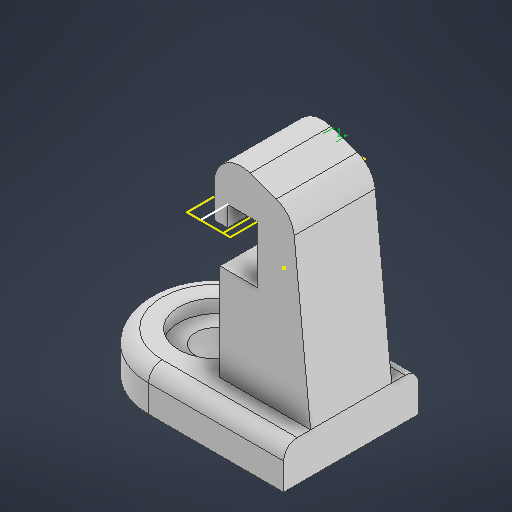
# Autodesk Inventor part: zaczep_baterie
Saved by Autodesk Inventor 2026.1 (Build 301233020, 233B)
## iProperties
Created: 2026-08-01
Part Number: zaczep_baterie
Material: Ogólny
Document SubType Name: Modeling
Designer: Nitro
Density: 1 g/cm^3
Appearance: Domyślna
Author: Nitro
Autodesk Inventor part; units mm, degrees
ref_plane "YZ Plane" through (0, 0, 0) normal (1, 0, 0) x (0, 1, 0)
ref_plane "XZ Plane" through (0, 0, 0) normal (0, 1, 0) x (-1, 0, 0)
ref_plane "XY Plane" through (0, 0, 0) normal (0, 0, 1) x (1, 0, 0)
sketch "Szkic1" plane through (0, 0, 0) normal (0, 1, 0) x (-1, 0, 0)
  line L0 (0, 0) -> (10, 0)
  line L1 (10, 0) -> (10, -10)
  line L2 (10, -10) -> (0, -10)
  line L3 (0, -10) -> (0, 0)
  arc A0 (10, -10) -> (10, 0) centre (10, -5) ccw
  circle A1 centre (10, -5) radius 1.5
  dimension "d0" = 10
  dimension "d1" = 10
  dimension "d2" = 3
  constraints: 8 end point, 2 centre point, 2 parallel, 2 point on circle, 2 tangent, 1 coincident, 1 horizontal, 1 perpendicular
  measures "d0" distance of L1.end L2.end
  measures "d1" distance of L0.end L1.end
  measures "d2" diameter of A1
extrude "Wyciągnięcie proste1" add sketch "Szkic1" along normal blind 3 contours L0 L1 A1 L2 L3 | A0 L1 A1
sketch "Szkic2" plane through (0, 0, -10) normal (0, 0, -1) x (-1, 0, 0)
  line L0 (0, 0) -> (10, 0) projected
  line L1 (10, 0) -> (10, 3) projected
  line L2 (0, 3) -> (10, 3) projected
  line L3 (0, 0) -> (0, 3) projected
  line L4 (10, 3) -> (0, 3) projected
  line L5 (0, 3) -> (1.3424, 16.1037)
  line L6 (1.3424, 16.1037) -> (7.148, 18.1599)
  line L7 (6.7175, 3) -> (6.7175, 10.1512)
  line L8 (6.7175, 10.1512) -> (3.9483, 10.1512)
  line L9 (3.9483, 10.1512) -> (3.9483, 14.3731)
  line L10 (3.9483, 14.3731) -> (7.148, 14.3731)
  line L11 (7.148, 14.3731) -> (7.148, 18.1599)
  constraints: 14 end point, 4 perpendicular, 1 point on line, 1 vertical
extrude "Wyciągnięcie proste2" add sketch "Szkic2" against normal blind 10 contours L5 L6 L11 L10 L9 L8 L7 L2
fillet "Zaokrąglenie1" radius 2 2 edges at (-1.3424, 16.1037, -5) (-7.148, 18.1599, -5)
sketch "Szkic3" plane through (0, 3, 0) normal (0, 1, 0) x (1, 0, 0)
  circle A0 centre (-10, 5) radius 1.5 projected
  line L0 (-6.7175, 0) -> (-6.7175, 10) projected
  line L1 (-6.7175, 10) -> (-10, 10) projected
  arc A1 (-10, 10) -> (-10, 0) centre (-10, 5) ccw projected
  line L2 (-10, 0) -> (-6.7175, 0) projected
  circle A2 centre (-10, 5) radius 2.75
  point P0 (0, 0)
  dimension "d8" = 5.5
  constraints: 1 centre point, 1 coincident
  measures "d8" diameter of A2
extrude "Wyciągnięcie proste3" cut sketch "Szkic3" against normal blind 1 contours A2
sketch "Szkic4" plane through (-7.148, 14.3731, -10) normal (0, -1, 0) x (1, 0, 0)
  line L0 (2.6677, 10) -> (2.6677, 0) projected
  line L1 (3.1997, 0) -> (0, 0) projected
  line L2 (3.1997, 0) -> (3.1997, 10) projected
  line L3 (0, 10) -> (3.1997, 10) projected
  line L4 (0, 0) -> (0, 10) projected
  line L5 (0, 10) -> (1, 10)
  line L6 (1, 10) -> (1, 0)
  line L7 (1, 0) -> (0, 0)
  line L8 (0, 0) -> (0, 10)
  point P0 (7.148, 10)
  dimension "d11" = 1
  constraints: 8 end point, 2 parallel, 1 horizontal, 1 perpendicular, 1 point on line
  measures "d11" distance of L6.end L7.end
sketch "Szkic5" plane through (0, 0, -10) normal (0, 0, -1) x (-1, 0, 0)
  arc A0 (7.148, 15.3298) -> (4.4803, 17.2151) centre (5.148, 15.3298) ccw projected
  line L0 (4.4803, 17.2151) -> (2.5353, 16.5262) projected
  arc A1 (2.5353, 16.5262) -> (1.2134, 14.8448) centre (3.203, 14.641) ccw projected
  line L1 (1.2134, 14.8448) -> (0, 3) projected
  line L2 (0, 0) -> (0, 3) projected
  line L3 (0, 0) -> (10, 0) projected
  line L4 (10, 0) -> (10, 3) projected
  line L5 (6.7175, 3) -> (10, 3) projected
  line L6 (6.7175, 3) -> (6.7175, 10.1512) projected
  line L7 (6.7175, 10.1512) -> (3.9483, 10.1512) projected
  line L8 (3.9483, 10.1512) -> (3.9483, 14.3731) projected
  line L9 (3.9483, 14.3731) -> (7.148, 14.3731) projected
  line L10 (7.148, 14.3731) -> (7.148, 15.3298) projected
  line L11 (6.7175, 10.1512) -> (6.7175, 3) projected
  line L12 (6.7175, 3) -> (-3.4565, 3)
  line L13 (-3.4565, 3) -> (-3.4565, 21.4857)
  line L14 (-3.4565, 21.4857) -> (9.1493, 20.7248)
  line L15 (9.1493, 20.7248) -> (6.7175, 3)
  constraints: 8 end point, 1 horizontal, 1 perpendicular
extrude "Wyciągnięcie proste4" cut sketch "Szkic5" against normal blind 2 contours L10 L9 L8 L7 L6 L12 L1 A1 L0 A0 | A0 L0 A1 L1 L12 L13 L14 L15 L6 L7 L8 L9 L10
sketch "Szkic6" plane through (-10, 0, 0) normal (0, 0, 1) x (1, 0, 0)
  arc A0 (5.5197, 17.2151) -> (2.852, 15.3298) centre (4.852, 15.3298) ccw projected
  line L0 (2.852, 15.3298) -> (2.852, 14.3731) projected
  line L1 (2.852, 14.3731) -> (6.0517, 14.3731) projected
  line L2 (6.0517, 14.3731) -> (6.0517, 10.1512) projected
  line L3 (6.0517, 10.1512) -> (3.2825, 10.1512) projected
  line L4 (3.2825, 10.1512) -> (3.2825, 3) projected
  line L5 (0, 3) -> (3.2825, 3) projected
  line L6 (0, 0) -> (0, 3) projected
  line L7 (0, 0) -> (10, 0) projected
  line L8 (10, 0) -> (10, 3) projected
  line L9 (10, 3) -> (8.7866, 14.8448) projected
  arc A1 (8.7866, 14.8448) -> (7.4647, 16.5262) centre (6.797, 14.641) ccw projected
  line L10 (7.4647, 16.5262) -> (5.5197, 17.2151) projected
  line L11 (3.2825, 3) -> (14.7362, 3)
  line L12 (14.7362, 3) -> (14.4317, 20.5833)
  line L13 (14.4317, 20.5833) -> (-1.6563, 19.7566)
  line L14 (-1.6563, 19.7566) -> (3.2825, 3)
  constraints: 8 end point, 1 horizontal
extrude "Wyciągnięcie proste5" cut sketch "Szkic6" against normal blind 2 contours L10 A1 L9 L11 L4 L3 L2 L1 L0 A0
sketch "Szkic7" plane through (-7.148, 14.3731, -8) normal (0, -1, 0) x (1, 0, 0)
  line L0 (0, 0) -> (0, 6) projected
  line L1 (0, 0) -> (3.1997, 0) projected
  line L2 (0, 6) -> (1, 6)
  line L3 (1, 6) -> (1, 0)
  line L4 (1, 0) -> (0, 0)
  line L5 (0, 0) -> (0, 6)
  point P0 (7.148, 8)
  dimension "d16" = 1
  constraints: 8 end point, 2 parallel, 1 horizontal, 1 perpendicular, 1 point on line
  measures "d16" distance of L3.end L4.end
extrude "Wyciągnięcie proste6" add sketch "Szkic7" along normal blind 1.5
fillet "Zaokrąglenie2" radius 1 3 edges at (-15, 3, -5) (-5, 3, 0) (-5, 3, -10)
